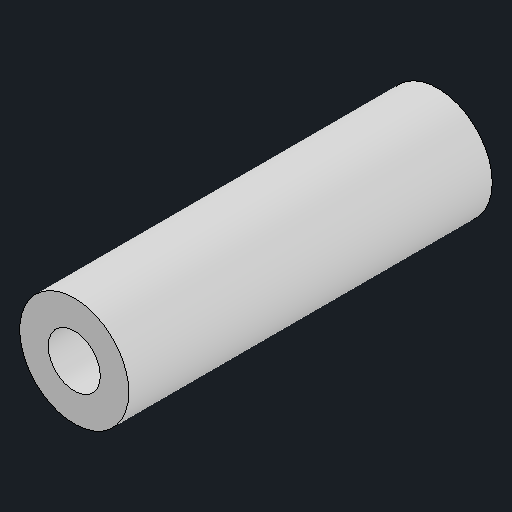
# Autodesk Inventor part: lead-screw-handwheel-grip
Saved by Autodesk Inventor 2027.1 (Build 311270010, 270A)
## iProperties
Created: 2026-11-06
Part Number: lead-screw-handwheel-grip
Material: Generic
Description: Concept: cylindrical crank grip with 4.3 mm through bore; rotation and M4 hardware to finalize
Document SubType Name: Modeling
Designer: queezz
Density: 1 g/cm^3
Appearance: Default
Author: queezz
Autodesk Inventor part; units mm, degrees
ref_plane "YZ Plane" through (0, 0, 0) normal (1, 0, 0) x (0, 1, 0)
ref_plane "XZ Plane" through (0, 0, 0) normal (0, 1, 0) x (-1, 0, 0)
ref_plane "Grip section plane" through (0, 0, 0) normal (0, 0, 1) x (1, 0, 0)
sketch "Grip section" plane through (0, 0, 0) normal (0, 0, 1) x (1, 0, 0)
  circle A0 centre (0, 0) radius 4.5
  circle A1 centre (0, 0) radius 2.15
  dimension "d0" = 9
  dimension "d1" = 4.3
  constraints: 2 centre point, 2 other
  measures "d0" diameter of A0
  measures "d1" diameter of A1
extrude "Grip body" add sketch "Grip section" along normal blind 30
equation "\"d0\" = grip_diameter"
equation "\"d1\" = grip_bore"
equation "\"d2\" = grip_length"
equation "\"grip_diameter\" = 9"
equation "\"grip_length\" = 30"
equation "\"grip_bore\" = 4.3"
body "Solid1"
